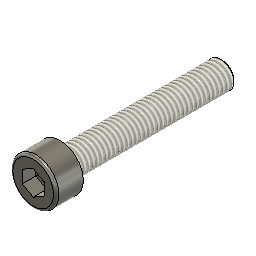
Full Assembly (Autodesk Fusion 360 archive; units mm, degrees)
design "Broached Hexagon Socket Head Cap Screw ANSI B18.3.1M - M5x0.8 x 30 Steel Grade 2 Plain"
description: Broached Hexagon Socket Head Cap Screw ANSI B18.3.1M - M5x0.8 x 30
part number: BSHCS ANSI B18.3.1M - M5x0.8 x 30 Steel Grade 2 Plain
Autodesk Fusion 360 part; units mm, degrees
sketch "Sketch1" plane through (0, 0, 0) normal (0, 1, 0) x (1, 0, 0)
  line L0 (-2.5, 0) -> (-2.5, 30)
  line L1 (-2.5, 30) -> (0, 30)
  line L2 (0, 30) -> (0, -5)
  line L3 (-2.5, 0) -> (-4.25, 0)
  line L4 (-4.25, 0) -> (-4.25, -5)
  line L5 (-4.25, -5) -> (0, -5)
  dimension "d101" = 30
  dimension "d102" = 5
  dimension "d109" = 8.5
  dimension "d110" = 5
  constraint perpendicular L0 L1
  constraint collinear origin L1.end L2.end
  constraint perpendicular L0 L3
  constraint coincident origin L3
  constraint vertical L2
  constraint coincident L2 L5.end
  constraint perpendicular L2 L5
  measures "d101" distance of origin L1
  measures "d102" distance of L3.end L5
revolve "Revolve1" add sketch "Sketch1" angle 360 about axis through (0, 0, -30) along (0, 0, 1)
ref_plane "WorkPlane1" through (0, 0, 5) normal (0, 0, 1) x (1, 0, 0)
sketch "Sketch6" plane through (0, 0, 5) normal (0, 0, 1) x (1, 0, 0)
  line L0 (0, -2.3094) -> (2, -1.1547)
  line L1 (2, -1.1547) -> (2, 1.1547)
  line L2 (2, 1.1547) -> (0, 2.3094)
  line L3 (0, 2.3094) -> (-2, 1.1547)
  line L4 (-2, 1.1547) -> (-2, -1.1547)
  line L5 (-2, -1.1547) -> (0, -2.3094)
  dimension "d111" = 4
  constraint vertical L1
  measures "d111" distance of L1 L4
extrude "Extrude1" cut sketch "Sketch6" against normal blind 2.5
extrude "Extrude2" cut 1 faces at (-0.6667, 0.3849, 2.5) along direction (0, 0, -1) blind 2.5 draft -85
thread "Thread3" "ANSI Metric M Profile 5.0 M5x0.8 M5x0.8 4g6g" major diameter 4.901 minor diameter 4.007 pitch 0.8 angle 60 resizes the face on face at (-2.4876, 0.2489, -20) from (0, 0, -1) to (0, 0, -30)
fillet "Fillet4" radius 0.5 1 edges at (-3.9624, 1.5369, 5)
sketch "Sketch7" plane through (0, 0, 0) normal (0, 1, 0) x (1, 0, 0)
  line L0 (-2.55, 30) -> (-2.55, 29.5092)
  line L1 (-2.55, 29.5092) -> (-2.0092, 30)
  line L2 (0, 30) -> (0, -5)
  line L3 (-2.55, 30) -> (0, 30)
  dimension "d104" = 2.0092
  dimension "d105" = 2.55
  dimension "d106" = 0.4908
  constraint coincident L2.start L3.end
  constraint perpendicular L2 L3
  constraint coincident L1.end L3
  constraint perpendicular L0 L3
  measures "d104" distance of L1.end L2
  measures "d105" distance of L0 L2.start
  measures "d106" distance of L0.end L3
revolve "Revolve3" cut sketch "Sketch7" angle 360 about axis through (0, 0, 1.75) along (0, 0, 1)
equation "adsk_nomlen = 30.00 mm"
equation "adsk_headh = 5.00 mm"
equation "adsk_headdia = 8.50 mm"
equation "adsk_nomdia = 5.00 mm"
equation "adsk_philwidth = 4.00 mm"
equation "d31 = -adsk_phildepth"
equation "adsk_phildepth = 2.50 mm"
equation "d71 = adsk_headh"
equation "d76 = -adsk_phildepth"
equation "adsk_thrlen = 29.00 mm"
equation "d86 = adsk_nomdia * 0.1"
equation "adsk_startlen = 0.49076 mm"
equation "adsk_endpointdia = 4.01848 mm"
equation "d101 = adsk_nomlen"
equation "d102 = adsk_headh"
equation "d104 = adsk_endpointdia / 2"
equation "d105 = adsk_nomdia * 0.51"
equation "d106 = adsk_startlen"
equation "d108 = min(adsk_thrlen; adsk_nomlen - 0.001 mm)"
equation "d109 = adsk_headdia"
equation "d110 = adsk_nomdia"
equation "d111 = adsk_philwidth"

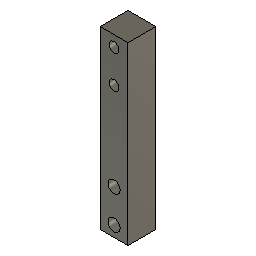
design "Load Cell"
part number: 2026-09-26-17-26-46-482
Autodesk Fusion 360 part; units mm, degrees
sketch "Sketch1" plane through (0, 0, 0) normal (0, 0, 1) x (1, 0, 0)
  line L0 (6.35, -6.35) -> (-6.35, -6.35)
  line L1 (-6.35, -6.35) -> (-6.35, 6.35)
  line L2 (-6.35, 6.35) -> (6.35, 6.35)
  line L3 (6.35, 6.35) -> (6.35, -6.35)
  line L4 (6.35, -6.35) -> (-6.35, 6.35) construction
  line L5 (-6.35, -6.35) -> (6.35, 6.35) construction
  dimension "d1" = 12.7
  dimension "d2" = 12.7
  constraint horizontal L0
  constraint perpendicular L0 L1
  constraint parallel L0 L2
  constraint parallel L1 L3
  constraint coincident L4 origin
  constraint coincident L5 origin
  measures "d1" distance of L1.end L2.end
  measures "d2" distance of L0.end L1.end
extrude "Extrude1" add sketch "Sketch1" along normal blind 80
sketch "Sketch2" plane through (0, -6.35, 0) normal (0, -1, 0) x (1, 0, 0)
  line L0 (-6.35, 0) -> (6.35, 0)
  line L1 (6.35, 0) -> (6.35, 80)
  line L2 (6.35, 80) -> (-6.35, 80)
  line L3 (-6.35, 80) -> (-6.35, 0)
  circle A0 centre (0, 5) radius 2.75
  circle A1 centre (0, 20) radius 2.75
  circle A2 centre (0, 75) radius 2.25
  circle A3 centre (0, 60) radius 2.25
  dimension "d5" = 5.5
  dimension "d6" = 5
  dimension "d7" = 5.5
  dimension "d8" = 15
  dimension "d9" = 4.5
  dimension "d10" = 5
  dimension "d11" = 4.5
  dimension "d12" = 15
  measures "d5" diameter of A0
  measures "d6" distance of origin A0.centre
  measures "d7" diameter of A1
  measures "d8" distance of A0.centre A1.centre
  measures "d9" diameter of A2
  measures "d10" distance of L2 A2.centre
  measures "d11" diameter of A3
  measures "d12" distance of A2.centre A3.centre
extrude "Extrude2" cut sketch "Sketch2" against normal blind 20 contours A0 | A1 | A2 | A3

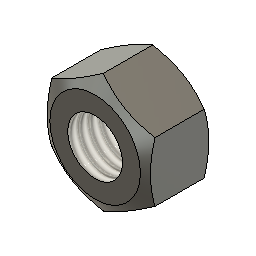
design "Hex Nut Style 2 ANSI B18.2.4.2M - M5x0.8 Steel Grade 2H Plain"
description: Hex Nut Style 2 ANSI B18.2.4.2M - M5x0.8
part number: HNS2 ANSI B18.2.4.2M - M5x0.8 Steel Grade 2H Plain
Autodesk Fusion 360 part; units mm, degrees
sketch "Sketch1" plane through (0, 0, 0) normal (0, 1, 0) x (1, 0, 0)
  line L0 (0, 0) -> (0, -5.1)
  line L1 (-2.5, 0) -> (-3.5, 0)
  line L2 (-3.5, 0) -> (-4.62, -0.6466)
  line L3 (-4.62, -0.6466) -> (-4.62, -4.4534)
  line L4 (-4.62, -4.4534) -> (-3.5, -5.1)
  line L5 (-3.5, -5.1) -> (-2.5, -5.1)
  line L6 (-2.5, -5.1) -> (-2.5, 0)
  dimension "d121" = 5
  dimension "d122" = 30
  dimension "d123" = 30
  dimension "d125" = 7
  dimension "d128" = 9.24
  dimension "d153" = 5.1
  constraint vertical L0
  constraint coincident L0 L0.end
  constraint coincident origin L0
  constraint coincident L0.start L1
  constraint coincident L0.start origin
  constraint vertical L1.end L4.end
  constraint coincident L0.end L5
  constraint horizontal L1
  measures "d122" angle of L1 L2
  measures "d123" angle of L4 L5
  measures "d153" distance of L1 L5
revolve "Revolve1" add sketch "Sketch1" angle 360 about axis through (0, 0, 0) along (0, 0, 1)
sketch "Sketch8" plane through (0, 0, 5.1) normal (0, 0, 1) x (1, 0, 0)
  line L0 (-4, -2.3118) -> (-4, 2.3118)
  circle A0 centre (0, 0) radius 2.5
  circle A1 centre (0, 0) radius 4.62
  dimension "d114" = 4
  constraint coincident L0.end A1
  constraint coincident L0.start A1
  constraint vertical L0
  measures "d114" distance of A0.centre L0
extrude "Extrude5" cut sketch "Sketch8" against normal blind 5.1 contours L0 A1 picked at (-4.1, -0.5631)
pattern_circular "C-Pattern2" count 6 over 360 about axis through (0, 0, 1.75) along (0, 0, 1) of "Extrude5"
thread "Thread3" "ANSI Metric M Profile 5.0 M5x0.8 M5x0.8 6H" major diameter 5.12 minor diameter 4.234 pitch 0.8 angle 60 resizes the face on face at (-2.4969, 0.1246, 3.4)
equation "adsk_nheig = 5.10 mm"
equation "adsk_maxdia = 9.24 mm"
equation "adsk_nomdia = 5.00 mm"
equation "d89 = -adsk_nheig"
equation "adsk_waflat = 8.00 mm"
equation "d114 = adsk_waflat / 2"
equation "adsk_chamang1 = 30 deg"
equation "adsk_chamang2 = 30 deg"
equation "d121 = adsk_nomdia"
equation "d122 = adsk_chamang1"
equation "d123 = adsk_chamang2"
equation "d125 = adsk_beardia"
equation "d128 = adsk_maxdia"
equation "d147 = adsk_nheig"
equation "adsk_beardia = 7.00 mm"
equation "d153 = adsk_nheig"

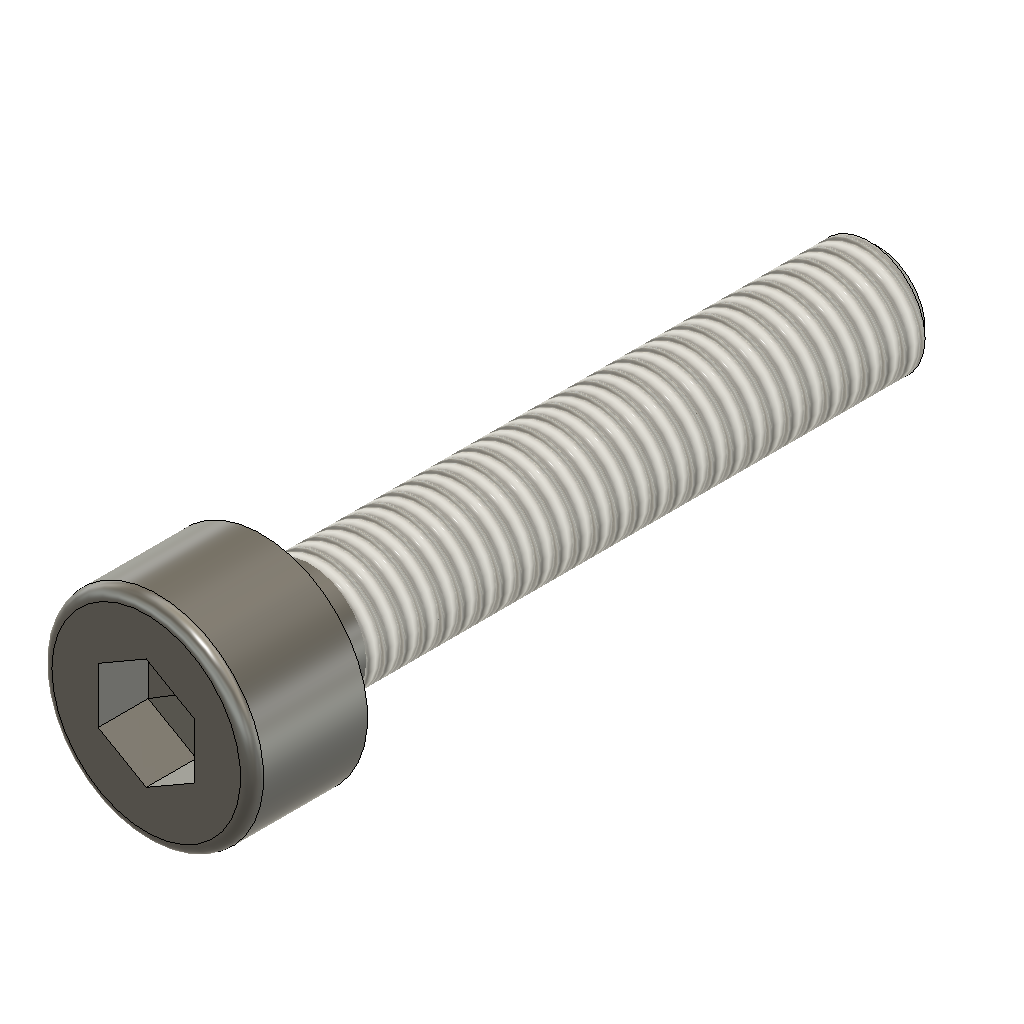
design "Hexagon Socket Head Cap Screw ISO 4762 - M3 x 16 Steel 4.6 Plain"
description: Hexagon Socket Head Cap Screw ISO 4762 - M3 x 16
part number: ISO 4762 - M3 x 16 Steel 4.6 Plain
Autodesk Fusion 360 part; units mm, degrees
sketch "Sketch1" plane through (0, 0, 0) normal (0, 1, 0) x (1, 0, 0)
  line L0 (-1.5, 0) -> (-1.5, 16)
  line L1 (-1.5, 16) -> (0, 16)
  line L2 (0, 16) -> (0, -3)
  line L3 (-1.5, 0) -> (-2.75, 0)
  line L4 (-2.75, 0) -> (-2.75, -3)
  line L5 (-2.75, -3) -> (0, -3)
  dimension "d9" = 3
  dimension "d106" = 3
  dimension "d107" = 16
  dimension "d116" = 5.5
  constraint perpendicular L0 L1
  constraint collinear origin L1.end L2.end
  constraint perpendicular L0 L3
  constraint coincident origin L3
  constraint vertical L2
  constraint coincident L2 L5.end
  constraint perpendicular L2 L5
  measures "d106" distance of L3 L5
  measures "d107" distance of origin L1
revolve "Revolve1" add sketch "Sketch1" angle 360 about axis through (0, 0, -16) along (0, 0, 1)
ref_plane "WorkPlane1" through (0, 0, 3) normal (0, 0, 1) x (1, 0, 0)
sketch "Sketch6" plane through (0, 0, 3) normal (0, 0, 1) x (1, 0, 0)
  line L0 (-1.25, 0.7217) -> (-1.25, -0.7217)
  line L1 (-1.25, -0.7217) -> (0, -1.4434)
  line L2 (0, -1.4434) -> (1.25, -0.7217)
  line L3 (1.25, -0.7217) -> (1.25, 0.7217)
  line L4 (1.25, 0.7217) -> (0, 1.4434)
  line L5 (0, 1.4434) -> (-1.25, 0.7217)
  dimension "d117" = 2.5
  constraint vertical L0
  measures "d117" distance of L0 L3
extrude "Extrude1" cut sketch "Sketch6" against normal blind 1.3
extrude "Extrude2" cut 1 faces at (-0.4167, 0.2406, 1.7) along direction (0, 0, -1) blind 1.3 draft -85
fillet "Fillet4" radius 0.3 1 edges at (-2.5639, 0.9944, 3)
thread "Thread3" "ISO Metric profile 3.0 M3x0.5 M3x0.5 6g" major diameter 2.927 minor diameter 2.3555 pitch 0.5 angle 60 resizes the face on face at (-1.4925, 0.1494, -10.6667) from (0, 0, -1.25) to (0, 0, -16)
sketch "Sketch7" plane through (0, 0, 0) normal (0, 1, 0) x (1, 0, 0)
  line L0 (-1.53, 16) -> (-1.53, 15.7)
  line L1 (-1.53, 15.7) -> (-1.23, 16)
  line L2 (0, 16) -> (0, -3)
  line L3 (-1.53, 16) -> (0, 16)
  dimension "d101" = 45
  dimension "d112" = 0.3
  dimension "d113" = 1.53
  constraint coincident L2.start L3.end
  constraint perpendicular L2 L3
  constraint coincident L1.end L3
  constraint perpendicular L0 L3
  measures "d101" angle of L0 L1
  measures "d112" distance of L0.end L3
  measures "d113" distance of L0 L2.start
revolve "Revolve3" cut sketch "Sketch7" angle 360 about axis through (0, 0, 1.75) along (0, 0, 1)
equation "d9 = adsk_nomdia"
equation "adsk_nomlen = 16.00 mm"
equation "adsk_headh = 3.00 mm"
equation "adsk_headdia = 5.50 mm"
equation "adsk_nomdia = 3.00 mm"
equation "adsk_philwidth = 2.50 mm"
equation "d31 = -adsk_phildepth"
equation "adsk_phildepth = 1.30 mm"
equation "d71 = adsk_headh"
equation "d76 = -adsk_phildepth"
equation "adsk_thrlen = 14.75 mm"
equation "d86 = adsk_nomdia * 0.1"
equation "adsk_startang = 45.00 deg"
equation "d101 = adsk_startang"
equation "adsk_pitch1 = 0.50 mm"
equation "adsk_startlen = 0.30 mm"
equation "d106 = adsk_headh"
equation "d107 = adsk_nomlen"
equation "d112 = adsk_startlen"
equation "d113 = adsk_nomdia * 0.51"
equation "d115 = min(adsk_thrlen; adsk_nomlen - 0.001 mm)"
equation "d116 = adsk_headdia"
equation "d117 = adsk_philwidth"

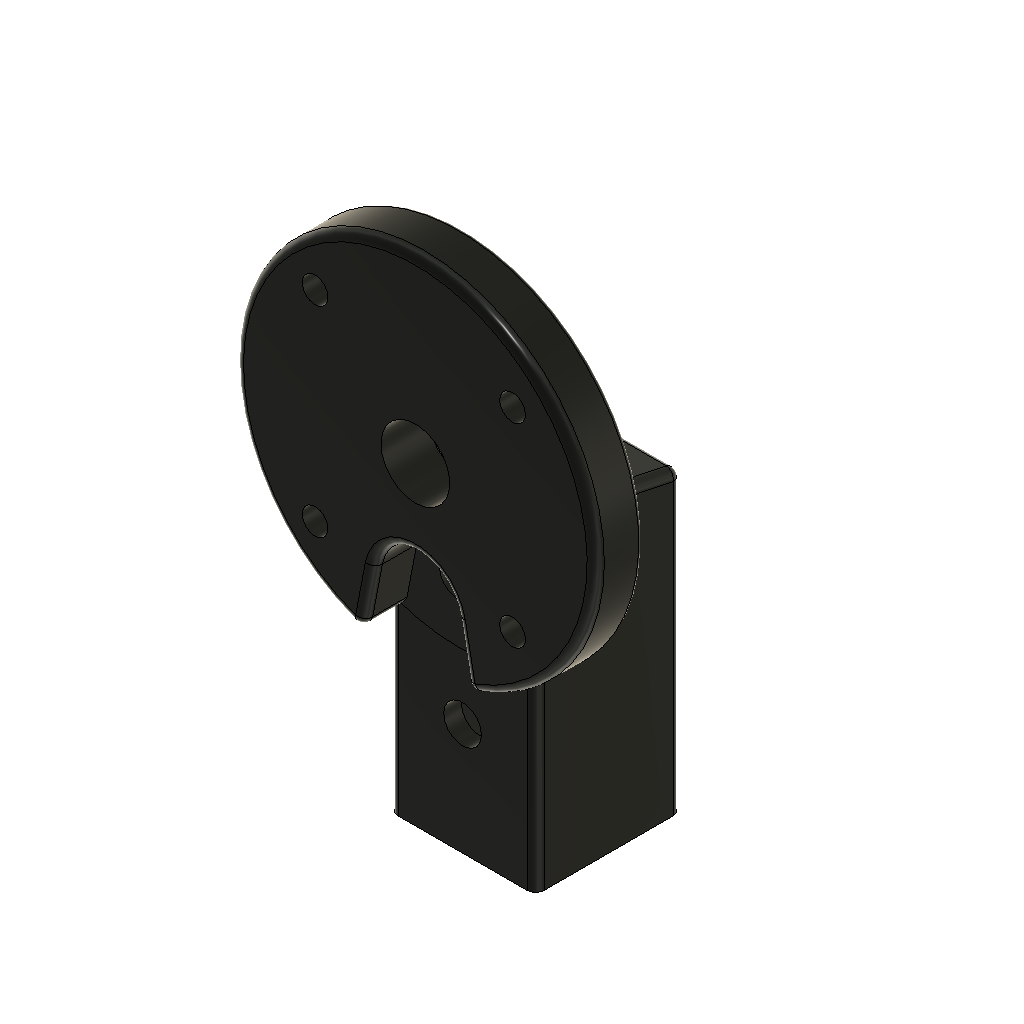
design "Motor Mount"
part number: 2026-09-26-16-22-31-044
Autodesk Fusion 360 part; units mm, degrees
sketch "Sketch1" plane through (0, 0, 0) normal (0, 1, 0) x (1, 0, 0)
  circle A0 centre (0, -16.5) radius 1.5
  circle A1 centre (0, 16) radius 1.5
  circle A2 centre (-16.5, 0) radius 1.5
  circle A3 centre (16, 0) radius 1.5
  circle A4 centre (0, 0) radius 21
  circle A5 centre (0, 0) radius 4
  line L0 (2.8284, 2.8284) -> (0, 0) construction
  dimension "d3" = 3
  dimension "d5" = 3
  dimension "d6" = 32.5
  dimension "d7" = 3
  dimension "d9" = 3
  dimension "d10" = 32.5
  dimension "d11" = 8
  constraint coincident A4.centre L0
  constraint coincident A4.centre A5.centre
  constraint coincident A5 L0.start
  measures "d3" diameter of A0
  measures "d5" diameter of A1
  measures "d6" distance of A0.centre A1.centre
  measures "d7" diameter of A2
  measures "d9" diameter of A3
  measures "d10" distance of A2.centre A3.centre
  measures "d11" diameter of A5
extrude "Extrude1" add sketch "Sketch1" against normal blind 5.5
move_body "Move1" bodies 1 to x (0.707107, 0, 0.707107) y (0, 1, 0) z (-0.707107, 0, 0.707107) at (0, 0, 0)
sketch "Sketch2" plane through (0, 0, 0) normal (0, 1, 0) x (-1, 0, 0)
  circle A0 centre (0, 0) radius 4
  circle A1 centre (-11.3137, 11.3137) radius 1.5
  circle A2 centre (-11.3137, -11.3137) radius 1.5
  circle A3 centre (11.6673, 11.6673) radius 1.5
  circle A4 centre (11.6673, -11.6673) radius 1.5
  circle A5 centre (0, 0) radius 21
  line L0 (8.5, -4.0291) -> (-8.5, -4.0291)
  line L1 (-8.5, -4.0291) -> (-8.5, -42.0291)
  line L2 (-8.5, -42.0291) -> (8.5, -42.0291)
  line L3 (8.5, -42.0291) -> (8.5, -4.0291)
  line L4 (8.5, -4.0291) -> (-8.5, -42.0291) construction
  line L5 (-8.5, -4.0291) -> (8.5, -42.0291) construction
  point P0 (0, -23.0291)
  dimension "d14" = 17
  dimension "d15" = 38
  constraint horizontal L0
  constraint perpendicular L0 L1
  constraint parallel L0 L2
  constraint parallel L1 L3
  constraint coincident L4 P0
  constraint coincident L5 P0
  measures "d14" distance of L1.end L2.end
  measures "d15" distance of L0.end L1.end
extrude "Extrude2" add sketch "Sketch2" along normal blind 17 contours A5 L0 L1 L3 | A5 L1 L2 L3 picked at (0, -9.6861)
sketch "Sketch3" plane through (0, 0, -42.0291) normal (0, 0, -1) x (1, 0, 0)
  line L0 (8.5, 0) -> (-8.5, 0)
  line L1 (-8.5, 0) -> (-8.5, -17)
  line L2 (-8.5, -17) -> (8.5, -17)
  line L3 (8.5, -17) -> (8.5, 0)
  line L4 (0, -17) -> (0, -8.5)
  line L5 (6.45, -14.95) -> (-6.45, -14.95)
  line L6 (-6.45, -14.95) -> (-6.45, -2.05)
  line L7 (-6.45, -2.05) -> (6.45, -2.05)
  line L8 (6.45, -2.05) -> (6.45, -14.95)
  line L9 (6.45, -14.95) -> (-6.45, -2.05) construction
  line L10 (-6.45, -14.95) -> (6.45, -2.05) construction
  point P0 (0, -8.5)
  dimension "d18" = 8.5
  dimension "d19" = 12.9
  dimension "d20" = 12.9
  constraint midpoint L2 L4.start
  constraint perpendicular L2 L4
  constraint horizontal L5
  constraint perpendicular L5 L6
  constraint parallel L5 L7
  constraint parallel L6 L8
  constraint coincident L9 P0
  constraint coincident L10 P0
  constraint coincident P0 L4.end
  measures "d18" distance of L4.start P0
  measures "d19" distance of L6.end L7.end
  measures "d20" distance of L5.end L6.end
extrude "Extrude3" cut sketch "Sketch3" against normal blind 34 contours L5 L6 L7 L8
sketch "Sketch4" plane through (0, 14.95, 0) normal (0, -1, 0) x (1, 0, 0)
  line L0 (-6.45, -42.0291) -> (6.45, -42.0291)
  line L1 (6.45, -42.0291) -> (6.45, -8.0291)
  line L2 (6.45, -8.0291) -> (-6.45, -8.0291)
  line L3 (-6.45, -8.0291) -> (-6.45, -42.0291)
  circle A0 centre (0, -14.0291) radius 2.2
  circle A1 centre (0, -29.0291) radius 2.2
  dimension "d23" = 4.4
  dimension "d24" = 6
  dimension "d25" = 4.4
  dimension "d26" = 15
  measures "d23" diameter of A0
  measures "d24" distance of L2 A0.centre
  measures "d25" diameter of A1
  measures "d26" distance of A0.centre A1.centre
extrude "Extrude4" cut sketch "Sketch4" along normal mid plane 60 contours A0 | A1
fillet "Fillet2" radius 0.5 1 edges at (0, 0, 21)
sketch "Sketch6" plane through (8.5, 0, 0) normal (1, 0, 0) x (0, 1, 0)
  line L0 (0, -19.2029) -> (0, -42.0291)
  line L1 (0, -42.0291) -> (17, -42.0291)
  line L2 (17, -42.0291) -> (17, -4.0291)
  line L3 (17, -4.0291) -> (0, -4.0291)
  line L4 (0, -4.0291) -> (0, -18.6548)
  spline S0 degree 3 poles (0, -18.6548) (0, -18.7245) (-0.0153, -18.8069) (-0.065, -18.9336) (-0.1072, -19.0013) (-0.196, -19.0951) (-0.2573, -19.1389) (-0.3697, -19.1879) (-0.4401, -19.2029) (-0.5, -19.2029) knots 0.233356 0.233356 0.233356 0.233356 0.254288 0.254288 0.274217 0.274217 0.293044 0.293044 0.311021 0.311021 0.311021 0.311021
  line L5 (-0.5, -19.2029) -> (0, -19.2029)
  line L6 (0, -4.0291) -> (17, -7.4997)
  line L7 (17, -4.0291) -> (17, -7.4997)
  line L8 (17, -4.0291) -> (0, -4.0291)
  constraint coincident L3.end L4.start
  constraint coincident L2 L6.end
  constraint coincident L2.end L3.start
extrude "Extrude7" cut sketch "Sketch6" against normal blind 20 contours L2 L3 L6 L7 L8
fillet "Fillet4" radius 1 11 edges at (0, 17, -7.4997) (8.5, 8.5, -5.7644) (-8.5, 8.5, -5.7644) (8.5, 17, -24.7644) (8.5, 0, -30.616) (8.5, -0.1391, -19.0342) (8.5, 0, -11.3419) (-8.5, 17, -24.7644) (-8.5, 0, -11.3419) (-8.5, -0.1391, -19.0342) (-8.5, 0, -30.616)
sketch "Sketch7" plane through (0, 0, 0) normal (0, 1, 0) x (-1, 0, 0)
  line L0 (9.5, -4.8456) -> (9.5, -18.1659)
  arc A0 (9.5, -18.1659) -> (-9.5, -18.1659) centre (0, 0) ccw
  line L1 (-9.5, -18.1659) -> (-9.5, -4.8456)
  spline S0 degree 3 poles (-9.5, -4.8456) (-9.4985, -4.8441) (-9.4971, -4.8427) (-9.3458, -4.6917) (-9.1929, -4.5529) (-8.8543, -4.3089) (-8.6743, -4.2076) (-8.2936, -4.0679) (-8.0981, -4.0291) (-7.9, -4.0291) knots -0.000618 -0.000618 -0.000618 -0.000618 0 0 0.063498 0.063498 0.126396 0.126396 0.186956 0.186956 0.186956 0.186956
  line L2 (-7.9, -4.0291) -> (7.9, -4.0291)
  spline S1 degree 3 poles (7.9, -4.0291) (8.0981, -4.0291) (8.2936, -4.0679) (8.6743, -4.2076) (8.8543, -4.3089) (9.1929, -4.5529) (9.3458, -4.6917) (9.4971, -4.8427) (9.4985, -4.8441) (9.5, -4.8456) knots 0 0 0 0 0.059415 0.059415 0.121125 0.121125 0.183423 0.183423 0.184029 0.184029 0.184029 0.184029
  circle A1 centre (0, 0) radius 4
  circle A2 centre (-11.3137, 11.3137) radius 1.5
  circle A3 centre (-11.3137, -11.3137) radius 1.5
  circle A4 centre (11.6673, 11.6673) radius 1.5
  circle A5 centre (11.6673, -11.6673) radius 1.5
  circle A6 centre (11.6673, -11.6673) radius 2.75
  circle A7 centre (-11.3137, -11.3137) radius 2.75
  dimension "d48" = 5.5
  dimension "d49" = 5.5
  constraint concentric A5 A6
  constraint concentric A3 A7
  measures "d48" diameter of A6
  measures "d49" diameter of A7
extrude "Extrude8" cut sketch "Sketch7" along normal blind 1 contours L0 A6 | L1 A7 picked at (9.3082, -11.7347) picked at (-9.3314, -11.8061)
chamfer "Chamfer1" distance 1 angle 45 4 edges at (6.45, 8.5, -42.0291) (0, 2.05, -42.0291) (0, 14.95, -42.0291) (-6.45, 8.5, -42.0291) tangent chain off
sketch "Sketch5" plane through (0, -5.5, 0) normal (0, -1, 0) x (1, 0, 0)
  circle A0 centre (0, 0) radius 4
  circle A1 centre (11.3137, 11.3137) radius 1.5
  circle A2 centre (11.3137, -11.3137) radius 1.5
  circle A3 centre (-11.6673, 11.6673) radius 1.5
  circle A4 centre (-11.6673, -11.6673) radius 1.5
  circle A5 centre (0, 0) radius 21
  circle A6 centre (0, -14) radius 4.925
  line L0 (-4.8356, -13.0658) -> (-6.1882, -20.0675)
  line L1 (4.8356, -13.0658) -> (6.1882, -20.0675)
  arc A7 (-6.1882, -20.0675) -> (6.1882, -20.0675) centre (0, 0) ccw
  dimension "d53" = 9.85
  constraint coincident A6 L0.start
  constraint coincident A5 L0.end
  constraint tangent A6 L0
  constraint coincident A6 L1.start
  constraint coincident A5 L1.end
  constraint tangent A6 L1
  measures "d53" diameter of A6
extrude "Extrude9" cut sketch "Sketch5" against normal blind 5 contours A5 A6 L0 L1 A7 | A6
fillet "Fillet5" radius 1 6 edges at (0, -5.5, 21) (-5.5119, -5.5, -16.5667) (0, -5.5, -9.075) (5.5119, -5.5, -16.5667) (6.1882, -3, -20.0675) (-6.1882, -3, -20.0675)

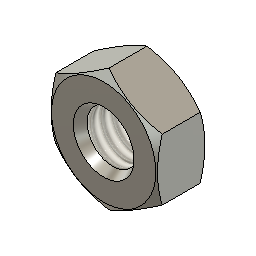
design "Hexagon Nut DIN 934 - M4 x 0.7 Steel 6 Plain"
description: Hexagon Nut DIN 934 - M4 x 0.7
part number: DIN 934 - M4 x 0.7 Steel 6 Plain
Autodesk Fusion 360 part; units mm, degrees
sketch "Sketch1" plane through (0, 0, 0) normal (0, 1, 0) x (1, 0, 0)
  line L0 (0, 0) -> (0, -3.2)
  line L1 (-2, 0) -> (-3.43, 0)
  line L2 (-3.43, 0) -> (-4.0425, -0.3536)
  line L3 (-4.0425, -0.3536) -> (-4.0425, -2.8464)
  line L4 (-4.0425, -2.8464) -> (-3.43, -3.2)
  line L5 (-3.43, -3.2) -> (-2, -3.2)
  line L6 (-2, -3.2) -> (-2, 0)
  dimension "d121" = 4
  dimension "d122" = 30
  dimension "d123" = 30
  dimension "d128" = 8.085
  dimension "d172" = 6.86
  dimension "d179" = 3.2
  constraint vertical L0
  constraint coincident L0 L0.end
  constraint coincident origin L0
  constraint horizontal L1
  constraint coincident L0.start L1
  constraint coincident L0.start origin
  constraint coincident L0.end L5
  constraint vertical L1.end L4.end
  measures "d122" angle of L1 L2
  measures "d123" angle of L4 L5
  measures "d179" distance of L1 L5
revolve "Revolve1" add sketch "Sketch1" angle 360 about axis through (0, 0, 0) along (0, 0, 1)
sketch "Sketch8" plane through (0, 0, 3.2) normal (0, 0, 1) x (1, 0, 0)
  line L0 (-3.5, -2.0228) -> (-3.5, 2.0228)
  circle A0 centre (0, 0) radius 2
  circle A1 centre (0, 0) radius 4.0425
  dimension "d114" = 3.5
  constraint coincident L0.end A1
  constraint coincident L0.start A1
  constraint vertical L0
  measures "d114" distance of A0.centre L0
extrude "Extrude5" cut sketch "Sketch8" against normal blind 3.2 contours L0 A1 picked at (-3.5875, -0.4927)
pattern_circular "C-Pattern2" count 6 over 360 about axis through (0, 0, 1.75) along (0, 0, 1) of "Extrude5"
thread "Thread3" "ISO Metric profile 4.0 M4x0.7 M4x0.7 6H" major diameter 4.1095 minor diameter 3.332 pitch 0.7 angle 60 resizes the face on face at (-1.9975, 0.0997, 2.1333)
sketch "Sketch12" plane through (0, 0, 0) normal (0, 1, 0) x (1, 0, 0)
  line L0 (-2, 0) -> (0, 0)
  line L1 (-1.0762, -1.6) -> (-2, 0)
  line L2 (-2, -3.2) -> (0, -3.2)
  line L3 (-1.0762, -1.6) -> (-2, -3.2)
  line L4 (0, 0) -> (0, -3.2)
  dimension "d169" = 60
  dimension "d177" = 2
  dimension "d178" = 60
  constraint horizontal L0
  constraint coincident L1.start L3.start
  constraint vertical L0.start L2.start
  constraint coincident L2.end L4.end
  constraint coincident L0.end L4.start
  constraint perpendicular L2 L4
  measures "d169" angle of L2 L3
  measures "d177" distance of L0.start L4
  measures "d178" angle of L0 L1
revolve "Revolve3" cut sketch "Sketch12" angle 360 about axis through (0, 0, 1.75) along (0, 0, 1)
equation "adsk_nheig = 3.20 mm"
equation "adsk_maxdia = 8.085 mm"
equation "adsk_nomdia = 4.00 mm"
equation "d89 = -adsk_nheig"
equation "adsk_waflat = 7.00 mm"
equation "d114 = adsk_waflat / 2"
equation "adsk_chamang1 = 30.00 deg"
equation "adsk_chamang2 = 30.00 deg"
equation "d121 = adsk_nomdia"
equation "d122 = adsk_chamang1"
equation "d123 = adsk_chamang2"
equation "d128 = adsk_maxdia"
equation "d163 = adsk_nheig"
equation "adsk_beardia = adsk_waflat * 0.98"
equation "d172 = adsk_beardia"
equation "d177 = adsk_nomdia * 0.5"
equation "d179 = adsk_nheig"

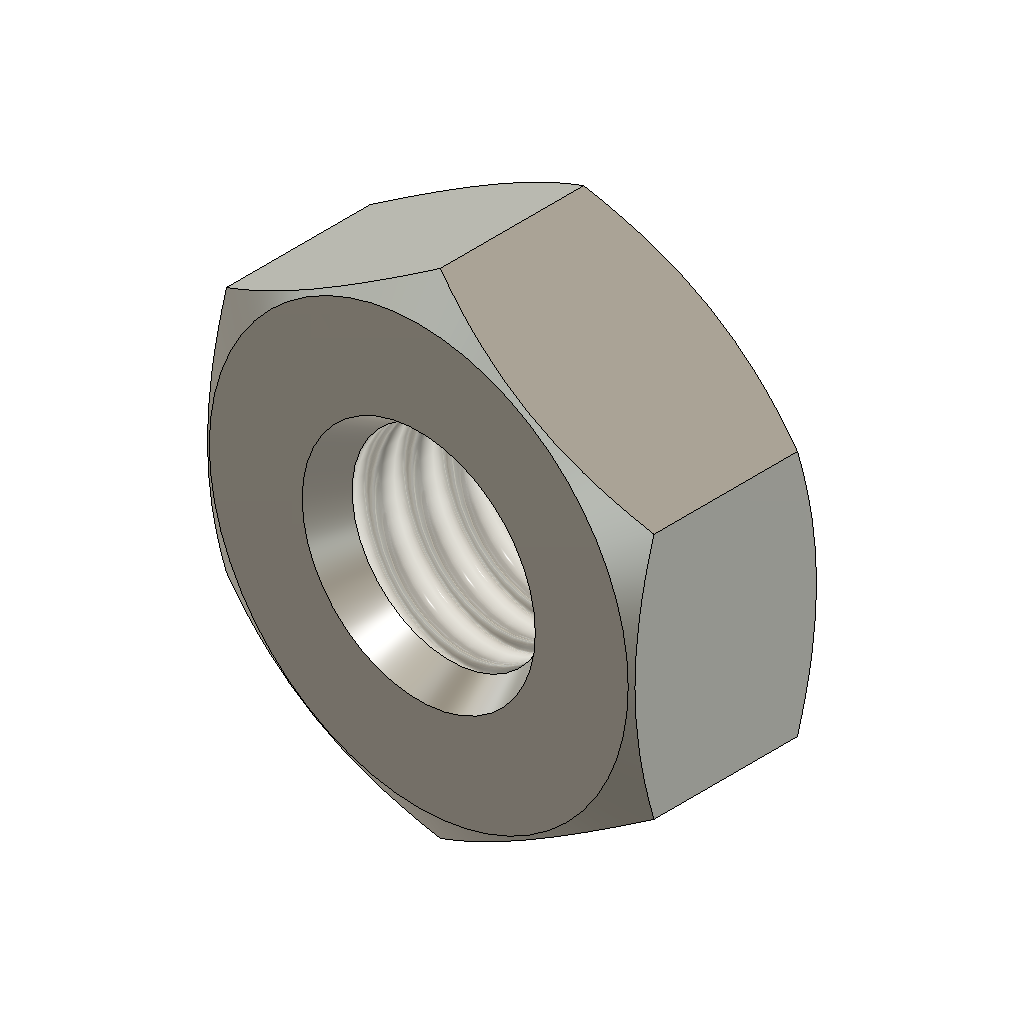
design "Hexagon Regular Nut ISO 4032 - M3 Steel 6 Plain"
description: Hexagon Regular Nut ISO 4032 - M3
part number: ISO 4032 - M3 Steel 6 Plain
Autodesk Fusion 360 part; units mm, degrees
sketch "Sketch1" plane through (0, 0, 0) normal (0, 1, 0) x (1, 0, 0)
  line L0 (0, 0) -> (0, -2.4)
  line L1 (-1.5, 0) -> (-2.695, 0)
  line L2 (-2.695, 0) -> (-3.1763, -0.2778)
  line L3 (-3.1763, -0.2778) -> (-3.1763, -2.1222)
  line L4 (-3.1763, -2.1222) -> (-2.695, -2.4)
  line L5 (-2.695, -2.4) -> (-1.5, -2.4)
  line L6 (-1.5, -2.4) -> (-1.5, 0)
  dimension "d121" = 3
  dimension "d122" = 30
  dimension "d123" = 30
  dimension "d128" = 6.3525
  dimension "d172" = 5.39
  dimension "d179" = 2.4
  constraint vertical L0
  constraint coincident L0 L0.end
  constraint coincident origin L0
  constraint horizontal L1
  constraint coincident L0.start L1
  constraint coincident L0.start origin
  constraint coincident L0.end L5
  constraint vertical L1.end L4.end
  measures "d122" angle of L1 L2
  measures "d123" angle of L4 L5
  measures "d179" distance of L1 L5
revolve "Revolve1" add sketch "Sketch1" angle 360 about axis through (0, 0, 0) along (0, 0, 1)
sketch "Sketch8" plane through (0, 0, 2.4) normal (0, 0, 1) x (1, 0, 0)
  line L0 (-2.75, -1.5894) -> (-2.75, 1.5894)
  circle A0 centre (0, 0) radius 1.5
  circle A1 centre (0, 0) radius 3.1763
  dimension "d114" = 2.75
  constraint coincident L0.end A1
  constraint coincident L0.start A1
  constraint vertical L0
  measures "d114" distance of A0.centre L0
extrude "Extrude5" cut sketch "Sketch8" against normal blind 2.4 contours L0 A1 picked at (-2.8188, -0.3871)
pattern_circular "C-Pattern2" count 6 over 360 about axis through (0, 0, 1.75) along (0, 0, 1) of "Extrude5"
thread "Thread3" "ISO Metric profile 3.0 M3x0.5 M3x0.5 6H" major diameter 3.086 minor diameter 2.529 pitch 0.5 angle 60 resizes the face on face at (-1.4925, 0.1494, 1.6)
sketch "Sketch12" plane through (0, 0, 0) normal (0, 1, 0) x (1, 0, 0)
  line L0 (-1.5, 0) -> (0, 0)
  line L1 (-0.8072, -1.2) -> (-1.5, 0)
  line L2 (-1.5, -2.4) -> (0, -2.4)
  line L3 (-0.8072, -1.2) -> (-1.5, -2.4)
  line L4 (0, 0) -> (0, -2.4)
  dimension "d169" = 60
  dimension "d177" = 1.5
  dimension "d178" = 60
  constraint horizontal L0
  constraint coincident L1.start L3.start
  constraint vertical L0.start L2.start
  constraint coincident L2.end L4.end
  constraint coincident L0.end L4.start
  constraint perpendicular L2 L4
  measures "d169" angle of L2 L3
  measures "d177" distance of L0.start L4
  measures "d178" angle of L0 L1
revolve "Revolve3" cut sketch "Sketch12" angle 360 about axis through (0, 0, 1.75) along (0, 0, 1)
equation "adsk_nheig = 2.40 mm"
equation "adsk_maxdia = 6.3525 mm"
equation "adsk_nomdia = 3.00 mm"
equation "d89 = -adsk_nheig"
equation "adsk_waflat = 5.50 mm"
equation "d114 = adsk_waflat / 2"
equation "adsk_chamang1 = 30.00 deg"
equation "adsk_chamang2 = 30.00 deg"
equation "d121 = adsk_nomdia"
equation "d122 = adsk_chamang1"
equation "d123 = adsk_chamang2"
equation "d128 = adsk_maxdia"
equation "d163 = adsk_nheig"
equation "adsk_beardia = 5.39 mm"
equation "d172 = adsk_beardia"
equation "d177 = adsk_nomdia * 0.5"
equation "d179 = adsk_nheig"
